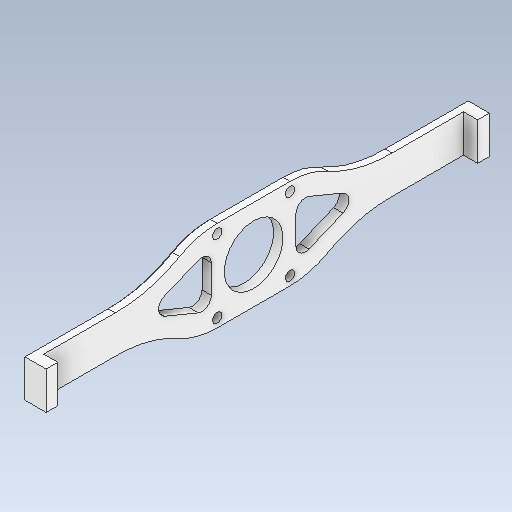
# Autodesk Inventor part: stand12
Saved by Autodesk Inventor 2026.2 (Build 302298010, 298A)
## iProperties
Created: 2026-04-29
Part Number: stand12
Material: ABS 플라스틱
Document SubType Name: Modeling
Designer: work
Density: 1.06 g/cm^3
Appearance: 매끄러움 - 흰색
Author: work
Autodesk Inventor part; units mm, degrees
ref_plane "YZ Plane" through (0, 0, 0) normal (1, 0, 0) x (0, 1, 0)
ref_plane "XZ Plane" through (0, 0, 0) normal (0, 1, 0) x (-1, 0, 0)
ref_plane "XY Plane" through (0, 0, 0) normal (0, 0, 1) x (1, 0, 0)
sketch "스케치1" plane through (0, 0, 0) normal (1, 0, 0) x (0, 1, 0)
  circle A0 centre (0, 0) radius 12.5
  line L0 (-15.5, 15.5) -> (15.5, 15.5) construction
  line L1 (15.5, 15.5) -> (15.5, -15.5) construction
  line L2 (15.5, -15.5) -> (-15.5, -15.5) construction
  line L3 (-15.5, -15.5) -> (-15.5, 15.5) construction
  line L4 (-15.5, 15.5) -> (15.5, -15.5) construction
  line L5 (15.5, 15.5) -> (-15.5, -15.5) construction
  circle A1 centre (0, -59) radius 8
  line L6 (8, -89.4) -> (-8, -89.4)
  line L7 (-8, -89.4) -> (-8, -59)
  line L8 (8, -59) -> (8, -89.4)
  line L9 (15.5, 0) -> (-15.5, 0) construction
  circle A2 centre (15.5, -15.5) radius 2
  circle A3 centre (-15.5, -15.5) radius 2
  line L10 (19.271, 0) -> (19.271, -15.5)
  line L11 (-18.5, 0) -> (-18.5, -15.6832)
  arc A4 (15.063, -31.5338) -> (19.271, -15.5) centre (-13.3802, -15.5) ccw
  arc A5 (15.063, -31.5338) -> (8, -59) centre (62.823, -58.4567) ccw
  line L12 (0, -59) -> (0, 0) construction
  line L13 (15.5, -15.5) -> (19.271, -15.5) construction
  line L14 (8, -89.4) -> (-8, -89.4)
  line L15 (-8, -89.4) -> (-8, -94.4)
  line L16 (-8, -94.4) -> (8, -94.4)
  line L17 (8, -94.4) -> (8, -89.4)
  arc A6 (-19.271, -15.5) -> (-15.063, -31.5338) centre (13.3802, -15.5) ccw
  arc A7 (-8, -59) -> (-15.063, -31.5338) centre (-62.823, -58.4567) ccw
  line L18 (0, -18) -> (12, -18)
  line L19 (12, -18) -> (0, -47)
  arc A8 (-8, -59) -> (-15.063, -31.5338) centre (-62.823, -58.4567) ccw
  line L20 (0, -18) -> (-12, -18)
  line L21 (-12, -18) -> (0, -47)
  circle A9 centre (0, 59) radius 8
  line L22 (8, 89.4) -> (-8, 89.4)
  line L23 (-8, 89.4) -> (-8, 59)
  line L24 (8, 59) -> (8, 89.4)
  line L25 (19.271, 0) -> (19.271, 15.5)
  line L26 (-18.5, 0) -> (-18.5, 15.6832)
  arc A10 (19.271, 15.5) -> (15.063, 31.5338) centre (-13.3802, 15.5) ccw
  arc A11 (8, 59) -> (15.063, 31.5338) centre (62.823, 58.4567) ccw
  line L27 (0, 59) -> (0, 0) construction
  line L28 (8, 89.4) -> (-8, 89.4)
  line L29 (-8, 89.4) -> (-8, 94.4)
  line L30 (-8, 94.4) -> (8, 94.4)
  line L31 (8, 94.4) -> (8, 89.4)
  arc A12 (-15.063, 31.5338) -> (-19.271, 15.5) centre (13.3802, 15.5) ccw
  arc A13 (-15.063, 31.5338) -> (-8, 59) centre (-62.823, 58.4567) ccw
  line L32 (0, 18) -> (12, 18)
  line L33 (12, 18) -> (0, 47)
  line L34 (0, 18) -> (-12, 18)
  line L35 (-12, 18) -> (0, 47)
  arc A14 (-15.063, 31.5338) -> (-8, 59) centre (-62.823, 58.4567) ccw
  line L36 (-19.2705, 15.6832) -> (-19.2705, -16.3168)
  circle A15 centre (15.5, 15.5) radius 2
  circle A16 centre (-15.5, 15.5) radius 2
  point P0 (7.9988, 58.8616)
  point P1 (-7.9988, 58.8616)
  point P2 (-19.2705, -15.6832)
  point P3 (-7.9988, -58.8616)
  point P4 (7.9988, -58.8616)
  dimension "d0" = 25
  dimension "d1" = 31
  dimension "d2" = 31
  dimension "d3" = 16
  dimension "d4" = 59
  dimension "d5" = 89.4
  dimension "d6" = 4
  dimension "d7" = 4
  dimension "d8" = 3
  dimension "d9" = 3.771
  dimension "d10" = 5
  dimension "d11" = 16
  dimension "d12" = 16
  dimension "d13" = 12
  dimension "d14" = 18
  dimension "d15" = 12
  dimension "d16" = 32
  dimension "d17" = 19.2705
  dimension "d18" = 4
  dimension "d19" = 4
  constraints: 76 end point, 29 point on circle, 28 symmetric about line, 17 centre point, 6 parallel, 5 coincident, 5 midpoint, 5 point on line, 4 horizontal, 3 tangent, 2 perpendicular, 2 vertical, 9 other
  measures "d0" diameter of A0
  measures "d1" distance of L1.end L2.end
  measures "d2" distance of L0.end L1.end
  measures "d3" diameter of A1
  measures "d4" distance of L12.start point (0, 0)
  measures "d5" distance from line of point (0, 0) L6
  measures "d6" diameter of A2
  measures "d7" diameter of A3
  measures "d8" distance between parallel lines of L11 L3
  measures "d9" distance between parallel lines of L1 L10
  measures "d10" distance of L14.end L15.end
  measures "d11" distance of L15.end L16.end
  measures "d12" distance between parallel lines of L7 L8
  measures "d13" distance of L12.start L19.end
  measures "d14" distance from line of point (0, 0) L18
  measures "d15" distance of L18.start L18.end
  measures "d16" distance of L36.start L36.end
  measures "d17" distance from line of point (0, 0) L36
  measures "d18" diameter of A15
  measures "d19" diameter of A16
extrude "돌출1" add sketch "스케치1" along normal blind 4 contours A1 A7 A6 L36 A12 A13 A9 A11 A10 L25 L10 A4 A5
extrude "돌출2" add sketch "스케치1" along normal blind 4 contours L8 L6 L7 A1 | A9 L23 L22 L24
extrude "돌출3" add sketch "스케치1" along normal blind 10 contours L17 L16 L15 L6 | L22 L29 L30 L31
fillet "모깎기1" radius 4 6 edges at (2, 12, 18) (2, 0, 47) (2, -12, 18) (2, -12, -18) (2, 12, -18) (2, 0, -47)
chamfer "모따기1" distance 1 angle 45 15 edges at (0, -19.2705, 0) (0, -18.1781, 23.877) (0, -18.1781, -23.877) (0, -9.7421, -44.7353) (0, -8, -76.7) (0, -8, 76.7) (0, 9.7248, 44.8023) (0, 18.2015, 23.7884) (0, 19.271, 0) (0, 18.2015, -23.7884) (0, 7.9994, -58.9308) (0, 8, 76.7) (0, 0, 94.4) (0, 8, -76.7) (0, 0, -94.4)
